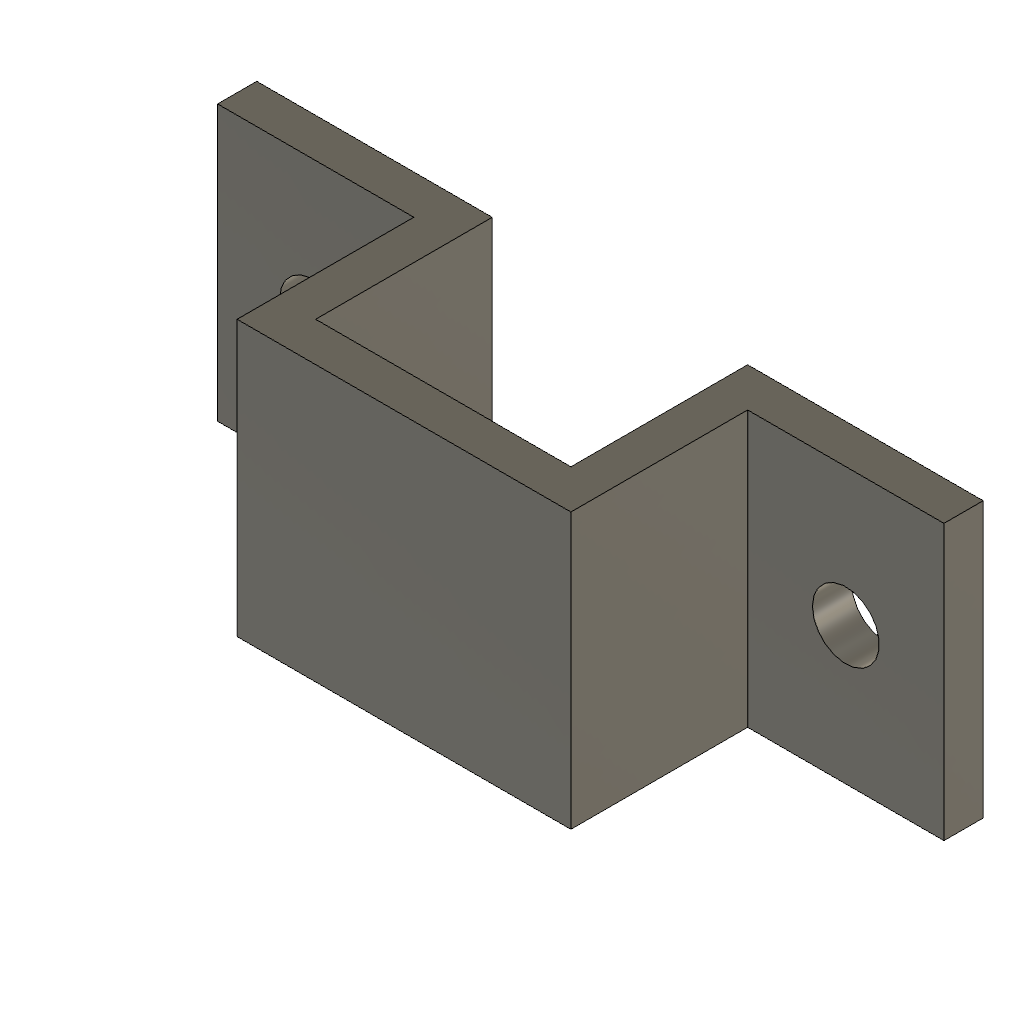
LFR Bracket (Autodesk Fusion 360 design; units mm, degrees)
part number: 2026-11-09-21-24-36-651
Autodesk Fusion 360 part; units mm, degrees
sketch "Sketch1" plane through (0, 5, 0) normal (0, 1, 0) x (-1, 0, 0)
  line L0 (3.1623, -23.15) -> (3.1623, -9.9043)
  arc A0 (3.1623, -9.9043) -> (3.0438, -9.6184) centre (2.7579, -9.9043) ccw
  arc A1 (3.0438, -9.6184) -> (2.7579, -9.5) centre (2.7579, -9.9043) ccw
  line L1 (2.7579, -9.5) -> (-2.7579, -9.5)
  arc A2 (-2.7579, -9.5) -> (-3.0438, -9.6184) centre (-2.7579, -9.9043) ccw
  arc A3 (-3.0438, -9.6184) -> (-3.1623, -9.9043) centre (-2.7579, -9.9043) ccw
  line L2 (-3.1623, -9.9043) -> (-3.1623, -23.15)
  line L3 (-3.1623, -23.15) -> (3.1623, -23.15)
  arc A4 (2.75, -13.5) -> (2.25, -13.5) centre (2.5, -13.5) ccw
  line L4 (2.75, -13.5) -> (2.75, -17.5)
  arc A5 (2.25, -17.5) -> (2.75, -17.5) centre (2.5, -17.5) ccw
  line L5 (2.25, -17.5) -> (2.25, -13.5)
  line L6 (-2.75, -17.5) -> (-2.75, -13.5)
  arc A6 (-2.25, -13.5) -> (-2.75, -13.5) centre (-2.5, -13.5) ccw
  line L7 (-2.25, -13.5) -> (-2.25, -17.5)
  arc A7 (-2.75, -17.5) -> (-2.25, -17.5) centre (-2.5, -17.5) ccw
sketch "Sketch2" plane through (0, 0, 0) normal (1, 0, 0) x (0, 1, 0)
sketch "Sketch3" plane through (0, 5, 0) normal (0, 1, 0) x (-1, 0, 0)
sketch "Sketch4" plane through (0, 0, 0) normal (0, 1, 0) x (1, 0, 0)
  line L0 (-30, -5) -> (-47, -5)
  line L1 (-47, -5) -> (-47, 9)
  line L2 (-47, 9) -> (-30, 9)
  line L3 (-30, 9) -> (-30, -5)
  dimension "d1" = 17
  dimension "d2" = 14
  constraint horizontal L0
  constraint vertical L1
  constraint horizontal L2
  constraint vertical L3
  measures "d1" distance of L0.start L0.end
  measures "d2" distance of L0.start L2.end
extrude "Extrude1" add sketch "Sketch4" along normal blind 3
extrude "Extrude2" cut 1 faces at (-35.6667, 3, 0.3333) along direction (0, -1, 0) blind 1
sketch "Sketch5" plane through (0, 2, 0) normal (0, 1, 0) x (-1, 0, 0)
  line L0 (30, -9) -> (47, -9)
  line L1 (47, -9) -> (47, 5)
  line L2 (47, 5) -> (30, 5)
  line L3 (30, 5) -> (30, -9)
  line L4 (30, 5) -> (32, 5)
  line L5 (32, 5) -> (32, -9)
  line L6 (32, -9) -> (30, -9)
  line L7 (30, -9) -> (30, 5)
  line L8 (47, 5) -> (45, 5)
  line L9 (45, 5) -> (45, -9)
  line L10 (45, -9) -> (47, -9)
  line L11 (47, -9) -> (47, 5)
  constraint horizontal L4
  constraint vertical L5
  constraint horizontal L6
  constraint vertical L7
  constraint coincident L0 L5.end
  constraint coincident L2.end L3.start
  constraint horizontal L8
  constraint vertical L9
  constraint horizontal L10
  constraint vertical L11
  constraint coincident L0 L9.end
  constraint coincident L1.end L2.start
extrude "Extrude3" add sketch "Sketch5" along normal blind 9 contours L0 L2 L3 L4 L5 L6 L7 | L0 L1 L2 L8 L9 L10 L11
sketch "Sketch6" plane through (-47, 0, 0) normal (-1, 0, 0) x (0, -1, 0)
  line L0 (-11, -9) -> (0, -9)
  line L1 (0, -9) -> (0, 5)
  line L2 (0, 5) -> (-11, 5)
  line L3 (-11, 5) -> (-11, -9)
  line L4 (-11, -9) -> (-9, -9)
  line L5 (-9, -9) -> (-9, 5)
  line L6 (-9, 5) -> (-11, 5)
  line L7 (-11, 5) -> (-11, -9)
  constraint horizontal L4
  constraint vertical L5
  constraint horizontal L6
  constraint vertical L7
  constraint coincident L2 L5.end
  constraint coincident L0.start L3.end
extrude "Extrude4" add sketch "Sketch6" along normal blind 10 contours L0 L2 L3 L4 L5 L6 L7
sketch "Sketch7" plane through (-30, 0, 0) normal (1, 0, 0) x (0, 1, 0)
  line L0 (11, 5) -> (0, 5)
  line L1 (0, 5) -> (0, -9)
  line L2 (0, -9) -> (11, -9)
  line L3 (11, -9) -> (11, 5)
  line L4 (11, 5) -> (9, 5)
  line L5 (9, 5) -> (9, -9)
  line L6 (9, -9) -> (11, -9)
  line L7 (11, -9) -> (11, 5)
  constraint horizontal L4
  constraint vertical L5
  constraint horizontal L6
  constraint vertical L7
  constraint coincident L2 L5.end
  constraint coincident L0.start L3.end
extrude "Extrude5" add sketch "Sketch7" along normal blind 10 contours L0 L2 L3 L4 L5 L6 L7
sketch "Sketch8" plane through (0, 9, 0) normal (0, -1, 0) x (1, 0, 0)
  line L0 (-47, -9) -> (-47, 5)
  line L1 (-47, 5) -> (-57, 5)
  line L2 (-57, 5) -> (-57, -9)
  line L3 (-57, -9) -> (-47, -9)
  circle A0 centre (-52.1303, -2) radius 1.7
  circle A1 centre (-25, -2) radius 1.7
  dimension "d13" = 3.4
  dimension "d14" = 3.4
  measures "d13" diameter of A0
  measures "d14" diameter of A1
extrude "Extrude6" cut sketch "Sketch8" against normal blind 2 contours A0 | A1
